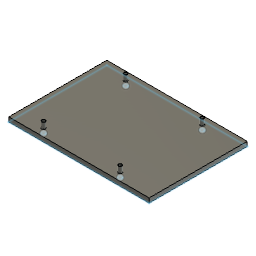
MainBoard_Support_V1 (Autodesk Fusion 360 design; units mm, degrees)
part number: 2026-04-16-23-41-08-305
Autodesk Fusion 360 part; units mm, degrees
sketch "Sketch1" plane through (0, 0, 0) normal (0, 1, 0) x (1, 0, 0)
  line L0 (4.4595, -5.6331) -> (161.8595, -5.6331)
  line L1 (161.8595, -5.6331) -> (161.8595, -115.6331)
  line L2 (161.8595, -115.6331) -> (4.4595, -115.6331)
  line L3 (4.4595, -115.6331) -> (4.4595, -5.6331)
  circle A0 centre (35, -15) radius 2
  circle A1 centre (120.7498, -14.9998) radius 2
  circle A2 centre (35, -107) radius 2
  circle A3 centre (120.75, -107) radius 2
  dimension "d1" = 157.4
  dimension "d2" = 110
  dimension "d3" = 4
  dimension "d4" = 4
  dimension "d5" = 4
  dimension "d6" = 4
  constraint horizontal L0
  constraint vertical L1
  constraint horizontal L2
  constraint vertical L3
  measures "d1" distance of L0.start L0.end
  measures "d2" distance of L0.start L2.end
  measures "d3" diameter of A0
  measures "d4" diameter of A1
  measures "d5" diameter of A2
  measures "d6" diameter of A3
extrude "Extrude1" add sketch "Sketch1" along normal blind 12 contours A0 makes body 1
extrude "Extrude2" add sketch "Sketch1" along normal blind 12 separate body contours A1 makes body 2
extrude "Extrude3" add sketch "Sketch1" along normal blind 12 separate body contours A2 makes body 3
extrude "Extrude4" add sketch "Sketch1" along normal blind 12 separate body contours A3 makes body 4
extrude "Extrude5" add sketch "Sketch1" along normal blind 5 bodies 1 2 3 4
hole "Hole2" at (35, 12, 15) direction (0, -1, 0) diameter 3 depth 6 tip angle 180 bodies 1
hole "Hole3" at (120.7498, 12, 14.9998) direction (0, -1, 0) diameter 3 depth 6 tip angle 180 bodies 1
hole "Hole4" at (35, 12, 107) direction (0, -1, 0) diameter 3 depth 6 tip angle 180 bodies 1
hole "Hole5" at (120.75, 12, 107) direction (0, -1, 0) diameter 3 depth 6 tip angle 180 bodies 1
sketch "Sketch2" plane through (0, 0, 0) normal (0, 1, 0) x (1, 0, 0)
